Autodesk Fusion 360 part; units mm, degrees
(part 9 of 28)
  line L943 (81.3236, 21.4891) -> (81.4328, 21.505)
  line L944 (81.4328, 21.505) -> (82.9265, 21.505)
  line L945 (82.9265, 21.505) -> (88.0242, 26.6027)
  line L946 (88.0242, 26.6027) -> (88.0832, 26.6545)
  line L947 (88.0832, 26.6545) -> (88.2189, 26.7328)
  line L948 (88.2189, 26.7328) -> (88.3702, 26.7733)
  line L949 (88.3702, 26.7733) -> (88.4485, 26.7785)
  line L950 (88.4485, 26.7785) -> (102.7125, 26.7785)
  line L951 (102.7125, 26.7785) -> (102.7355, 26.8129)
  line L952 (102.7355, 26.8129) -> (102.8741, 26.9515)
  line L953 (102.8741, 26.9515) -> (103.0371, 27.0604)
  line L954 (103.0371, 27.0604) -> (103.2182, 27.1354)
  line L955 (103.2182, 27.1354) -> (103.4105, 27.1737)
  line L956 (103.4105, 27.1737) -> (103.5085, 27.1785)
  line L957 (103.5085, 27.1785) -> (104.7085, 27.1785)
  line L958 (104.7085, 27.1785) -> (104.8065, 27.1737)
  line L959 (104.8065, 27.1737) -> (104.9988, 27.1354)
  line L960 (104.9988, 27.1354) -> (105.1799, 27.0604)
  line L961 (105.1799, 27.0604) -> (105.3429, 26.9515)
  line L962 (105.3429, 26.9515) -> (105.4815, 26.8129)
  line L963 (105.4815, 26.8129) -> (105.5045, 26.7785)
  line L964 (105.5045, 26.7785) -> (107.3522, 26.7785)
  line L965 (107.3522, 26.7785) -> (107.9218, 27.3481)
  line L966 (107.9218, 27.3481) -> (107.9808, 27.3998)
  line L967 (107.9808, 27.3998) -> (108.1165, 27.4782)
  line L968 (108.1165, 27.4782) -> (108.2678, 27.5187)
  line L969 (108.2678, 27.5187) -> (108.3461, 27.5238)
  line L970 (108.3461, 27.5238) -> (112.2749, 27.5238)
  line L971 (112.2749, 27.5238) -> (112.3532, 27.5187)
  line L972 (32.7136, 22.7426) -> (32.9001, 22.682)
  line L973 (32.9001, 22.682) -> (33.0749, 22.5929)
  line L974 (33.0749, 22.5929) -> (33.2336, 22.4776)
  line L975 (33.2336, 22.4776) -> (33.3723, 22.3389)
  line L976 (33.3723, 22.3389) -> (33.4876, 22.1802)
  line L977 (33.4876, 22.1802) -> (33.5766, 22.0055)
  line L978 (33.5766, 22.0055) -> (33.6372, 21.8189)
  line L979 (33.6372, 21.8189) -> (33.6679, 21.6252)
  line L980 (33.6679, 21.6252) -> (33.6718, 21.5271)
  line L981 (33.6718, 21.5271) -> (33.6718, 21.0271)
  line L982 (33.6718, 21.0271) -> (33.6679, 20.929)
  line L983 (33.6679, 20.929) -> (33.6372, 20.7353)
  line L984 (33.6372, 20.7353) -> (33.5766, 20.5488)
  line L985 (33.5766, 20.5488) -> (33.4876, 20.374)
  line L986 (33.4876, 20.374) -> (33.3723, 20.2153)
  line L987 (33.3723, 20.2153) -> (33.2336, 20.0766)
  line L988 (33.2336, 20.0766) -> (33.0749, 19.9613)
  line L989 (33.0749, 19.9613) -> (32.9001, 19.8723)
  line L990 (32.9001, 19.8723) -> (32.7136, 19.8117)
  line L991 (32.7136, 19.8117) -> (32.5198, 19.781)
  line L992 (32.5198, 19.781) -> (32.3237, 19.781)
  line L993 (32.3237, 19.781) -> (32.13, 19.8117)
  line L994 (32.13, 19.8117) -> (31.9434, 19.8723)
  line L995 (31.9434, 19.8723) -> (31.7686, 19.9613)
  line L996 (31.7686, 19.9613) -> (31.61, 20.0766)
  line L997 (31.61, 20.0766) -> (31.4713, 20.2153)
  line L998 (31.4713, 20.2153) -> (31.356, 20.374)
  line L999 (31.356, 20.374) -> (31.2669, 20.5488)
  line L1000 (31.2669, 20.5488) -> (31.2063, 20.7353)
  line L1001 (31.2063, 20.7353) -> (31.1756, 20.929)
  line L1002 (31.1756, 20.929) -> (31.1718, 21.0271)
  line L1003 (31.1718, 21.0271) -> (31.1718, 21.5271)
  line L1004 (31.1718, 21.5271) -> (31.1756, 21.6252)
  line L1005 (31.1756, 21.6252) -> (31.2063, 21.8189)
  line L1006 (31.2063, 21.8189) -> (31.2669, 22.0055)
  line L1007 (31.2669, 22.0055) -> (31.356, 22.1802)
  line L1008 (31.356, 22.1802) -> (31.4713, 22.3389)
  line L1009 (31.4713, 22.3389) -> (31.61, 22.4776)
  line L1010 (31.61, 22.4776) -> (31.7686, 22.5929)
  line L1011 (31.7686, 22.5929) -> (31.9434, 22.682)
  line L1012 (31.9434, 22.682) -> (32.13, 22.7426)
  line L1013 (32.13, 22.7426) -> (32.3237, 22.7733)
  line L1014 (32.3237, 22.7733) -> (32.5198, 22.7733)
  line L1015 (32.5198, 22.7733) -> (32.7136, 22.7426)
  line L1016 (93.6736, 22.7426) -> (93.8601, 22.682)
  line L1017 (93.8601, 22.682) -> (94.0349, 22.5929)
  line L1018 (94.0349, 22.5929) -> (94.1936, 22.4776)
  line L1019 (94.1936, 22.4776) -> (94.3323, 22.3389)
  line L1020 (94.3323, 22.3389) -> (94.4476, 22.1802)
  line L1021 (94.4476, 22.1802) -> (94.5366, 22.0055)
  line L1022 (94.5366, 22.0055) -> (94.5972, 21.8189)
  line L1023 (94.5972, 21.8189) -> (94.6279, 21.6252)
  line L1024 (94.6279, 21.6252) -> (94.6318, 21.5271)
  line L1025 (94.6318, 21.5271) -> (94.6318, 21.0271)
  line L1026 (94.6318, 21.0271) -> (94.6279, 20.929)
  line L1027 (94.6279, 20.929) -> (94.5972, 20.7353)
  line L1028 (94.5972, 20.7353) -> (94.5366, 20.5488)
  line L1029 (94.5366, 20.5488) -> (94.4476, 20.374)
  line L1030 (94.4476, 20.374) -> (94.3323, 20.2153)
  line L1031 (94.3323, 20.2153) -> (94.1936, 20.0766)
  line L1032 (94.1936, 20.0766) -> (94.0349, 19.9613)
  line L1033 (94.0349, 19.9613) -> (93.8601, 19.8723)
  line L1034 (93.8601, 19.8723) -> (93.6736, 19.8117)
  line L1035 (93.6736, 19.8117) -> (93.4798, 19.781)
  line L1036 (93.4798, 19.781) -> (93.2837, 19.781)
  line L1037 (93.2837, 19.781) -> (93.09, 19.8117)
  line L1038 (93.09, 19.8117) -> (92.9034, 19.8723)
  line L1039 (92.9034, 19.8723) -> (92.7286, 19.9613)
  line L1040 (92.7286, 19.9613) -> (92.57, 20.0766)
  line L1041 (92.57, 20.0766) -> (92.4313, 20.2153)
  line L1042 (92.4313, 20.2153) -> (92.316, 20.374)
  line L1043 (92.316, 20.374) -> (92.2269, 20.5488)
  line L1044 (92.2269, 20.5488) -> (92.1663, 20.7353)
  line L1045 (92.1663, 20.7353) -> (92.1356, 20.929)
  line L1046 (92.1356, 20.929) -> (92.1318, 21.0271)
  line L1047 (92.1318, 21.0271) -> (92.1318, 21.5271)
  line L1048 (92.1318, 21.5271) -> (92.1356, 21.6252)
  line L1049 (92.1356, 21.6252) -> (92.1663, 21.8189)
  line L1050 (92.1663, 21.8189) -> (92.2269, 22.0055)
  line L1051 (92.2269, 22.0055) -> (92.316, 22.1802)
  line L1052 (92.316, 22.1802) -> (92.4313, 22.3389)
  line L1053 (92.4313, 22.3389) -> (92.57, 22.4776)
  line L1054 (92.57, 22.4776) -> (92.7286, 22.5929)
  line L1055 (92.7286, 22.5929) -> (92.9034, 22.682)
  line L1056 (92.9034, 22.682) -> (93.09, 22.7426)
  line L1057 (93.09, 22.7426) -> (93.2837, 22.7733)
  line L1058 (93.2837, 22.7733) -> (93.4798, 22.7733)
  line L1059 (93.4798, 22.7733) -> (93.6736, 22.7426)
  line L1060 (44.6903, 20.1434) -> (41.4903, 20.1434)
  line L1061 (41.4903, 20.1434) -> (41.4903, 22.1434)
  line L1062 (41.4903, 22.1434) -> (44.6903, 22.1434)
  line L1063 (44.6903, 22.1434) -> (44.6903, 20.1434)
  line L1064 (105.6503, 20.1434) -> (102.4503, 20.1434)
  line L1065 (102.4503, 20.1434) -> (102.4503, 22.1434)
  line L1066 (102.4503, 22.1434) -> (105.6503, 22.1434)
  line L1067 (105.6503, 22.1434) -> (105.6503, 20.1434)
  line L1068 (50.1338, 32.4063) -> (50.3204, 32.3457)
  line L1069 (50.3204, 32.3457) -> (50.4952, 32.2566)
  line L1070 (50.4952, 32.2566) -> (50.6538, 32.1413)
  line L1071 (50.6538, 32.1413) -> (50.7925, 32.0026)
  line L1072 (50.7925, 32.0026) -> (50.9078, 31.8439)
  line L1073 (50.9078, 31.8439) -> (50.9969, 31.6692)
  line L1074 (50.9969, 31.6692) -> (51.0386, 31.5408)
  line L1075 (51.0386, 31.5408) -> (52.8792, 31.5408)
  line L1076 (52.8792, 31.5408) -> (52.9575, 31.5357)
  line L1077 (52.9575, 31.5357) -> (53.1088, 31.4951)
  line L1078 (53.1088, 31.4951) -> (53.2444, 31.4168)
  line L1079 (53.2444, 31.4168) -> (53.3035, 31.3651)
  line L1080 (53.3035, 31.3651) -> (59.2476, 25.421)
  line L1081 (59.2476, 25.421) -> (59.2993, 25.3619)
  line L1082 (59.2993, 25.3619) -> (59.3373, 25.2962)
  line L1083 (59.3373, 25.2962) -> (59.3843, 25.2888)
  line L1084 (59.3843, 25.2888) -> (59.5671, 25.2294)
  line L1085 (59.5671, 25.2294) -> (59.7384, 25.1421)
  line L1086 (59.7384, 25.1421) -> (59.8939, 25.0291)
  line L1087 (59.8939, 25.0291) -> (60.0298, 24.8932)
  line L1088 (60.0298, 24.8932) -> (60.1428, 24.7377)
  line L1089 (60.1428, 24.7377) -> (60.2301, 24.5664)
  line L1090 (60.2301, 24.5664) -> (60.2895, 24.3836)
  line L1091 (60.2895, 24.3836) -> (60.3195, 24.1937)
  line L1092 (60.3195, 24.1937) -> (60.3195, 24.0015)
  line L1093 (60.3195, 24.0015) -> (60.2895, 23.8117)
  line L1094 (60.2895, 23.8117) -> (60.2301, 23.6288)
  line L1095 (60.2301, 23.6288) -> (60.1428, 23.4576)
  line L1096 (60.1428, 23.4576) -> (60.0298, 23.3021)
  line L1097 (60.0298, 23.3021) -> (59.8939, 23.1661)
  line L1098 (59.8939, 23.1661) -> (59.7384, 23.0531)
  line L1099 (59.7384, 23.0531) -> (59.5671, 22.9659)
  line L1100 (59.5671, 22.9659) -> (59.3843, 22.9065)
  line L1101 (59.3843, 22.9065) -> (59.1944, 22.8764)
  line L1102 (59.1944, 22.8764) -> (59.0983, 22.8726)
  line L1103 (59.0983, 22.8726) -> (58.5483, 22.8726)
  line L1104 (58.5483, 22.8726) -> (58.4522, 22.8764)
  line L1105 (58.4522, 22.8764) -> (58.2623, 22.9065)
  line L1106 (58.2623, 22.9065) -> (58.0795, 22.9659)
  line L1107 (58.0795, 22.9659) -> (57.9083, 23.0531)
  line L1108 (57.9083, 23.0531) -> (57.7527, 23.1661)
  line L1109 (57.7527, 23.1661) -> (57.6168, 23.3021)
  line L1110 (57.6168, 23.3021) -> (57.5038, 23.4576)
  line L1111 (57.5038, 23.4576) -> (57.4166, 23.6288)
  line L1112 (57.4166, 23.6288) -> (57.3572, 23.8117)
  line L1113 (57.3572, 23.8117) -> (57.3271, 24.0015)
  line L1114 (57.3271, 24.0015) -> (57.3271, 24.1937)
  line L1115 (57.3271, 24.1937) -> (57.3572, 24.3836)
  line L1116 (57.3572, 24.3836) -> (57.4166, 24.5664)
  line L1117 (57.4166, 24.5664) -> (57.5038, 24.7377)
  line L1118 (57.5038, 24.7377) -> (57.6168, 24.8932)
  line L1119 (57.6168, 24.8932) -> (57.7527, 25.0291)
  line L1120 (57.7527, 25.0291) -> (57.8626, 25.1089)
  line L1121 (57.8626, 25.1089) -> (52.6307, 30.3408)
  line L1122 (52.6307, 30.3408) -> (51.0386, 30.3408)
  line L1123 (51.0386, 30.3408) -> (50.9969, 30.2125)
  line L1124 (50.9969, 30.2125) -> (50.9078, 30.0377)
  line L1125 (50.9078, 30.0377) -> (50.7925, 29.879)
  line L1126 (50.7925, 29.879) -> (50.6538, 29.7403)
  line L1127 (50.6538, 29.7403) -> (50.4952, 29.625)
  line L1128 (50.4952, 29.625) -> (50.3204, 29.536)
  line L1129 (50.3204, 29.536) -> (50.1338, 29.4754)
  line L1130 (50.1338, 29.4754) -> (49.9401, 29.4447)
  line L1131 (49.9401, 29.4447) -> (49.744, 29.4447)
  line L1132 (49.744, 29.4447) -> (49.5502, 29.4754)
  line L1133 (49.5502, 29.4754) -> (49.3637, 29.536)
  line L1134 (49.3637, 29.536) -> (49.1889, 29.625)
  line L1135 (49.1889, 29.625) -> (49.0302, 29.7403)
  line L1136 (49.0302, 29.7403) -> (48.8915, 29.879)
  line L1137 (48.8915, 29.879) -> (48.7762, 30.0377)
  line L1138 (48.7762, 30.0377) -> (48.6872, 30.2125)
  line L1139 (48.6872, 30.2125) -> (48.6266, 30.399)
  line L1140 (48.6266, 30.399) -> (48.5959, 30.5927)
  line L1141 (48.5959, 30.5927) -> (48.592, 30.6908)
  line L1142 (48.592, 30.6908) -> (48.592, 31.1908)
  line L1143 (48.592, 31.1908) -> (48.5959, 31.2889)
  line L1144 (48.5959, 31.2889) -> (48.6266, 31.4826)
  line L1145 (48.6266, 31.4826) -> (48.6872, 31.6692)
  line L1146 (48.6872, 31.6692) -> (48.7762, 31.8439)
  line L1147 (48.7762, 31.8439) -> (48.8915, 32.0026)
  line L1148 (48.8915, 32.0026) -> (49.0302, 32.1413)
  line L1149 (49.0302, 32.1413) -> (49.1889, 32.2566)
  line L1150 (49.1889, 32.2566) -> (49.3637, 32.3457)
  line L1151 (49.3637, 32.3457) -> (49.5502, 32.4063)
  line L1152 (49.5502, 32.4063) -> (49.744, 32.437)
  line L1153 (49.744, 32.437) -> (49.9401, 32.437)
  line L1154 (49.9401, 32.437) -> (50.1338, 32.4063)
  line L1155 (111.0938, 32.4063) -> (111.2804, 32.3457)
  line L1156 (111.2804, 32.3457) -> (111.4552, 32.2566)
  line L1157 (111.4552, 32.2566) -> (111.6138, 32.1413)
  line L1158 (111.6138, 32.1413) -> (111.7525, 32.0026)
  line L1159 (111.7525, 32.0026) -> (111.8678, 31.8439)
  line L1160 (111.8678, 31.8439) -> (111.9569, 31.6692)
  line L1161 (111.9569, 31.6692) -> (111.9986, 31.5408)
  line L1162 (111.9986, 31.5408) -> (113.8392, 31.5408)
  line L1163 (113.8392, 31.5408) -> (113.9175, 31.5357)
  line L1164 (113.9175, 31.5357) -> (114.0688, 31.4951)
  line L1165 (114.0688, 31.4951) -> (114.2044, 31.4168)
  line L1166 (114.2044, 31.4168) -> (114.2635, 31.3651)
  line L1167 (114.2635, 31.3651) -> (120.2076, 25.421)
  line L1168 (120.2076, 25.421) -> (120.2593, 25.3619)
  line L1169 (120.2593, 25.3619) -> (120.2973, 25.2962)
  line L1170 (120.2973, 25.2962) -> (120.3443, 25.2888)
  line L1171 (120.3443, 25.2888) -> (120.5271, 25.2294)
  line L1172 (120.5271, 25.2294) -> (120.6984, 25.1421)
  line L1173 (120.6984, 25.1421) -> (120.8539, 25.0291)
  line L1174 (120.8539, 25.0291) -> (120.9898, 24.8932)
  line L1175 (120.9898, 24.8932) -> (121.1028, 24.7377)
  line L1176 (121.1028, 24.7377) -> (121.1901, 24.5664)
  line L1177 (121.1901, 24.5664) -> (121.2495, 24.3836)
  line L1178 (121.2495, 24.3836) -> (121.2795, 24.1937)
  line L1179 (121.2795, 24.1937) -> (121.2795, 24.0015)
  line L1180 (121.2795, 24.0015) -> (121.2495, 23.8117)
  line L1181 (121.2495, 23.8117) -> (121.1901, 23.6288)
  line L1182 (121.1901, 23.6288) -> (121.1028, 23.4576)
  line L1183 (121.1028, 23.4576) -> (120.9898, 23.3021)
  line L1184 (120.9898, 23.3021) -> (120.8539, 23.1661)
  line L1185 (120.8539, 23.1661) -> (120.6984, 23.0531)
  line L1186 (120.6984, 23.0531) -> (120.5271, 22.9659)
  line L1187 (120.5271, 22.9659) -> (120.3443, 22.9065)
  line L1188 (120.3443, 22.9065) -> (120.1544, 22.8764)
  line L1189 (120.1544, 22.8764) -> (120.0583, 22.8726)
  line L1190 (120.0583, 22.8726) -> (119.5083, 22.8726)
  line L1191 (119.5083, 22.8726) -> (119.4122, 22.8764)
  line L1192 (119.4122, 22.8764) -> (119.2223, 22.9065)
  line L1193 (119.2223, 22.9065) -> (119.0395, 22.9659)
  line L1194 (119.0395, 22.9659) -> (118.8683, 23.0531)
  line L1195 (118.8683, 23.0531) -> (118.7127, 23.1661)
  line L1196 (118.7127, 23.1661) -> (118.5768, 23.3021)
  line L1197 (118.5768, 23.3021) -> (118.4638, 23.4576)
  line L1198 (118.4638, 23.4576) -> (118.3766, 23.6288)
  line L1199 (118.3766, 23.6288) -> (118.3172, 23.8117)
  line L1200 (118.3172, 23.8117) -> (118.2871, 24.0015)
  line L1201 (118.2871, 24.0015) -> (118.2871, 24.1937)
  line L1202 (118.2871, 24.1937) -> (118.3172, 24.3836)
  line L1203 (118.3172, 24.3836) -> (118.3766, 24.5664)
  line L1204 (118.3766, 24.5664) -> (118.4638, 24.7377)
  line L1205 (118.4638, 24.7377) -> (118.5768, 24.8932)
  line L1206 (118.5768, 24.8932) -> (118.7127, 25.0291)
  line L1207 (118.7127, 25.0291) -> (118.8226, 25.1089)
  line L1208 (118.8226, 25.1089) -> (113.5907, 30.3408)
  line L1209 (113.5907, 30.3408) -> (111.9986, 30.3408)
  line L1210 (111.9986, 30.3408) -> (111.9569, 30.2125)
  line L1211 (111.9569, 30.2125) -> (111.8678, 30.0377)
  line L1212 (111.8678, 30.0377) -> (111.7525, 29.879)
  line L1213 (111.7525, 29.879) -> (111.6138, 29.7403)
  line L1214 (111.6138, 29.7403) -> (111.4552, 29.625)
  line L1215 (111.4552, 29.625) -> (111.2804, 29.536)
  line L1216 (111.2804, 29.536) -> (111.0938, 29.4754)
  line L1217 (111.0938, 29.4754) -> (110.9001, 29.4447)
  line L1218 (110.9001, 29.4447) -> (110.704, 29.4447)
  line L1219 (110.704, 29.4447) -> (110.5102, 29.4754)
  line L1220 (110.5102, 29.4754) -> (110.3237, 29.536)
  line L1221 (110.3237, 29.536) -> (110.1489, 29.625)
  line L1222 (110.1489, 29.625) -> (109.9902, 29.7403)
  line L1223 (109.9902, 29.7403) -> (109.8515, 29.879)
  line L1224 (109.8515, 29.879) -> (109.7362, 30.0377)
  line L1225 (109.7362, 30.0377) -> (109.6472, 30.2125)
  line L1226 (109.6472, 30.2125) -> (109.5866, 30.399)
  line L1227 (109.5866, 30.399) -> (109.5559, 30.5927)
  line L1228 (109.5559, 30.5927) -> (109.552, 30.6908)
  line L1229 (109.552, 30.6908) -> (109.552, 31.1908)
  line L1230 (109.552, 31.1908) -> (109.5559, 31.2889)
  line L1231 (109.5559, 31.2889) -> (109.5866, 31.4826)
  line L1232 (109.5866, 31.4826) -> (109.6472, 31.6692)
  line L1233 (109.6472, 31.6692) -> (109.7362, 31.8439)
  line L1234 (109.7362, 31.8439) -> (109.8515, 32.0026)
  line L1235 (109.8515, 32.0026) -> (109.9902, 32.1413)
  line L1236 (109.9902, 32.1413) -> (110.1489, 32.2566)
  line L1237 (110.1489, 32.2566) -> (110.3237, 32.3457)
  line L1238 (110.3237, 32.3457) -> (110.5102, 32.4063)
  line L1239 (110.5102, 32.4063) -> (110.704, 32.437)
  line L1240 (110.704, 32.437) -> (110.9001, 32.437)
  line L1241 (110.9001, 32.437) -> (111.0938, 32.4063)
  line L1242 (32.7136, 30.3626) -> (32.9001, 30.302)
  line L1243 (32.9001, 30.302) -> (33.0749, 30.2129)
  line L1244 (33.0749, 30.2129) -> (33.2336, 30.0976)
  line L1245 (33.2336, 30.0976) -> (33.3723, 29.9589)
  line L1246 (33.3723, 29.9589) -> (33.4876, 29.8002)
  line L1247 (33.4876, 29.8002) -> (33.5766, 29.6255)
  line L1248 (33.5766, 29.6255) -> (33.6372, 29.4389)
  line L1249 (33.6372, 29.4389) -> (33.6679, 29.2452)
  line L1250 (33.6679, 29.2452) -> (33.6718, 29.1471)
  line L1251 (33.6718, 29.1471) -> (33.6718, 28.6471)
  line L1252 (33.6718, 28.6471) -> (33.6679, 28.549)
  line L1253 (33.6679, 28.549) -> (33.6372, 28.3553)
  line L1254 (33.6372, 28.3553) -> (33.5766, 28.1688)
  line L1255 (33.5766, 28.1688) -> (33.4876, 27.994)
  line L1256 (33.4876, 27.994) -> (33.3723, 27.8353)
  line L1257 (33.3723, 27.8353) -> (33.2336, 27.6966)
  line L1258 (33.2336, 27.6966) -> (33.0749, 27.5813)
  line L1259 (33.0749, 27.5813) -> (32.9001, 27.4923)
  line L1260 (32.9001, 27.4923) -> (32.7136, 27.4317)
  line L1261 (32.7136, 27.4317) -> (32.5198, 27.401)
  line L1262 (32.5198, 27.401) -> (32.3237, 27.401)
  line L1263 (32.3237, 27.401) -> (32.13, 27.4317)
  line L1264 (32.13, 27.4317) -> (31.9434, 27.4923)
  line L1265 (31.9434, 27.4923) -> (31.7686, 27.5813)
  line L1266 (31.7686, 27.5813) -> (31.61, 27.6966)
  line L1267 (31.61, 27.6966) -> (31.4713, 27.8353)
  line L1268 (31.4713, 27.8353) -> (31.356, 27.994)
  line L1269 (31.356, 27.994) -> (31.2669, 28.1688)
  line L1270 (31.2669, 28.1688) -> (31.2063, 28.3553)
  line L1271 (31.2063, 28.3553) -> (31.1756, 28.549)
  line L1272 (31.1756, 28.549) -> (31.1718, 28.6471)
  line L1273 (31.1718, 28.6471) -> (31.1718, 29.1471)
  line L1274 (31.1718, 29.1471) -> (31.1756, 29.2452)
  line L1275 (31.1756, 29.2452) -> (31.2063, 29.4389)
  line L1276 (31.2063, 29.4389) -> (31.2669, 29.6255)
  line L1277 (31.2669, 29.6255) -> (31.356, 29.8002)
  line L1278 (31.356, 29.8002) -> (31.4713, 29.9589)
  line L1279 (31.4713, 29.9589) -> (31.61, 30.0976)
  line L1280 (31.61, 30.0976) -> (31.7686, 30.2129)
  line L1281 (31.7686, 30.2129) -> (31.9434, 30.302)
  line L1282 (31.9434, 30.302) -> (32.13, 30.3626)
  line L1283 (32.13, 30.3626) -> (32.3237, 30.3933)
  line L1284 (32.3237, 30.3933) -> (32.5198, 30.3933)
  line L1285 (32.5198, 30.3933) -> (32.7136, 30.3626)
  line L1286 (93.6736, 30.3626) -> (93.8601, 30.302)
  line L1287 (93.8601, 30.302) -> (94.0349, 30.2129)
  line L1288 (94.0349, 30.2129) -> (94.1936, 30.0976)
  line L1289 (94.1936, 30.0976) -> (94.3323, 29.9589)
  line L1290 (94.3323, 29.9589) -> (94.4476, 29.8002)
  line L1291 (94.4476, 29.8002) -> (94.5366, 29.6255)
  line L1292 (94.5366, 29.6255) -> (94.5972, 29.4389)
  line L1293 (94.5972, 29.4389) -> (94.6279, 29.2452)
  line L1294 (94.6279, 29.2452) -> (94.6318, 29.1471)
  line L1295 (94.6318, 29.1471) -> (94.6318, 28.6471)
  line L1296 (94.6318, 28.6471) -> (94.6279, 28.549)
  line L1297 (94.6279, 28.549) -> (94.5972, 28.3553)
  line L1298 (94.5972, 28.3553) -> (94.5366, 28.1688)
  line L1299 (94.5366, 28.1688) -> (94.4476, 27.994)
  line L1300 (94.4476, 27.994) -> (94.3323, 27.8353)
  line L1301 (94.3323, 27.8353) -> (94.1936, 27.6966)
  line L1302 (94.1936, 27.6966) -> (94.0349, 27.5813)
  line L1303 (94.0349, 27.5813) -> (93.8601, 27.4923)
  line L1304 (93.8601, 27.4923) -> (93.6736, 27.4317)
  line L1305 (93.6736, 27.4317) -> (93.4798, 27.401)
  line L1306 (93.4798, 27.401) -> (93.2837, 27.401)
  line L1307 (93.2837, 27.401) -> (93.09, 27.4317)
  line L1308 (93.09, 27.4317) -> (92.9034, 27.4923)
  line L1309 (92.9034, 27.4923) -> (92.7286, 27.5813)
  line L1310 (92.7286, 27.5813) -> (92.57, 27.6966)
  line L1311 (92.57, 27.6966) -> (92.4313, 27.8353)
  line L1312 (92.4313, 27.8353) -> (92.316, 27.994)
  line L1313 (92.316, 27.994) -> (92.2269, 28.1688)
  line L1314 (92.2269, 28.1688) -> (92.1663, 28.3553)
  line L1315 (92.1663, 28.3553) -> (92.1356, 28.549)
  line L1316 (92.1356, 28.549) -> (92.1318, 28.6471)
  line L1317 (92.1318, 28.6471) -> (92.1318, 29.1471)
  line L1318 (92.1318, 29.1471) -> (92.1356, 29.2452)
  line L1319 (92.1356, 29.2452) -> (92.1663, 29.4389)
  line L1320 (92.1663, 29.4389) -> (92.2269, 29.6255)
  line L1321 (92.2269, 29.6255) -> (92.316, 29.8002)
  line L1322 (92.316, 29.8002) -> (92.4313, 29.9589)
  line L1323 (92.4313, 29.9589) -> (92.57, 30.0976)
  line L1324 (92.57, 30.0976) -> (92.7286, 30.2129)
  line L1325 (92.7286, 30.2129) -> (92.9034, 30.302)
  line L1326 (92.9034, 30.302) -> (93.09, 30.3626)
  line L1327 (93.09, 30.3626) -> (93.2837, 30.3933)
  line L1328 (93.2837, 30.3933) -> (93.4798, 30.3933)
  line L1329 (93.4798, 30.3933) -> (93.6736, 30.3626)
  line L1330 (22.3742, 30.1765) -> (22.5641, 30.1465)
  line L1331 (22.5641, 30.1465) -> (22.7469, 30.0871)
  line L1332 (22.7469, 30.0871) -> (22.9182, 29.9998)
  line L1333 (22.9182, 29.9998) -> (23.0737, 29.8868)
  line L1334 (23.0737, 29.8868) -> (23.2096, 29.7509)
  line L1335 (23.2096, 29.7509) -> (23.3226, 29.5954)
  line L1336 (23.3226, 29.5954) -> (23.4099, 29.4241)
  line L1337 (23.4099, 29.4241) -> (23.4693, 29.2413)
  line L1338 (23.4693, 29.2413) -> (23.4993, 29.0514)
  line L1339 (23.4993, 29.0514) -> (23.4993, 28.8592)
  line L1340 (23.4993, 28.8592) -> (23.4693, 28.6693)
  line L1341 (23.4693, 28.6693) -> (23.4099, 28.4865)
  line L1342 (23.4099, 28.4865) -> (23.3226, 28.3153)
  line L1343 (23.3226, 28.3153) -> (23.2096, 28.1597)
  line L1344 (23.2096, 28.1597) -> (23.0737, 28.0238)
  line L1345 (23.0737, 28.0238) -> (22.9182, 27.9108)
  line L1346 (22.9182, 27.9108) -> (22.7469, 27.8236)
  line L1347 (22.7469, 27.8236) -> (22.5641, 27.7642)
  line L1348 (22.5641, 27.7642) -> (22.3742, 27.7341)
  line L1349 (22.3742, 27.7341) -> (22.2781, 27.7303)
  line L1350 (22.2781, 27.7303) -> (21.7281, 27.7303)
  line L1351 (21.7281, 27.7303) -> (21.632, 27.7341)
  line L1352 (21.632, 27.7341) -> (21.4421, 27.7642)
  line L1353 (21.4421, 27.7642) -> (21.2593, 27.8236)
  line L1354 (21.2593, 27.8236) -> (21.0881, 27.9108)
  line L1355 (21.0881, 27.9108) -> (20.9325, 28.0238)
  line L1356 (20.9325, 28.0238) -> (20.7966, 28.1597)
  line L1357 (20.7966, 28.1597) -> (20.6836, 28.3153)
  line L1358 (20.6836, 28.3153) -> (20.5964, 28.4865)
  line L1359 (20.5964, 28.4865) -> (20.537, 28.6693)
  line L1360 (20.537, 28.6693) -> (20.5069, 28.8592)
  line L1361 (20.5069, 28.8592) -> (20.5069, 29.0514)
  line L1362 (20.5069, 29.0514) -> (20.537, 29.2413)
  line L1363 (20.537, 29.2413) -> (20.5964, 29.4241)
  line L1364 (20.5964, 29.4241) -> (20.6836, 29.5954)
  line L1365 (20.6836, 29.5954) -> (20.7966, 29.7509)
  line L1366 (20.7966, 29.7509) -> (20.9325, 29.8868)
  line L1367 (20.9325, 29.8868) -> (21.0881, 29.9998)
  line L1368 (21.0881, 29.9998) -> (21.2593, 30.0871)
  line L1369 (21.2593, 30.0871) -> (21.4421, 30.1465)
  line L1370 (21.4421, 30.1465) -> (21.632, 30.1765)
  line L1371 (21.632, 30.1765) -> (21.7281, 30.1803)
  line L1372 (21.7281, 30.1803) -> (22.2781, 30.1803)
  line L1373 (22.2781, 30.1803) -> (22.3742, 30.1765)
  line L1374 (83.3342, 30.1765) -> (83.5241, 30.1465)
  line L1375 (83.5241, 30.1465) -> (83.7069, 30.0871)
  line L1376 (83.7069, 30.0871) -> (83.8782, 29.9998)
  line L1377 (83.8782, 29.9998) -> (84.0337, 29.8868)
  line L1378 (84.0337, 29.8868) -> (84.1696, 29.7509)
  line L1379 (84.1696, 29.7509) -> (84.2826, 29.5954)
  line L1380 (84.2826, 29.5954) -> (84.3699, 29.4241)
  line L1381 (84.3699, 29.4241) -> (84.4293, 29.2413)
  line L1382 (84.4293, 29.2413) -> (84.4593, 29.0514)
  line L1383 (84.4593, 29.0514) -> (84.4593, 28.8592)
  line L1384 (84.4593, 28.8592) -> (84.4293, 28.6693)
  line L1385 (84.4293, 28.6693) -> (84.3699, 28.4865)
  line L1386 (84.3699, 28.4865) -> (84.2826, 28.3153)
  line L1387 (84.2826, 28.3153) -> (84.1696, 28.1597)
  line L1388 (84.1696, 28.1597) -> (84.0337, 28.0238)
  line L1389 (84.0337, 28.0238) -> (83.8782, 27.9108)
  line L1390 (83.8782, 27.9108) -> (83.7069, 27.8236)
  line L1391 (83.7069, 27.8236) -> (83.5241, 27.7642)
  line L1392 (83.5241, 27.7642) -> (83.3342, 27.7341)
  line L1393 (83.3342, 27.7341) -> (83.2381, 27.7303)
  line L1394 (83.2381, 27.7303) -> (82.6881, 27.7303)
  line L1395 (82.6881, 27.7303) -> (82.592, 27.7341)
  line L1396 (82.592, 27.7341) -> (82.4021, 27.7642)
  line L1397 (82.4021, 27.7642) -> (82.2193, 27.8236)
  line L1398 (82.2193, 27.8236) -> (82.0481, 27.9108)
  line L1399 (82.0481, 27.9108) -> (81.8925, 28.0238)
  line L1400 (81.8925, 28.0238) -> (81.7566, 28.1597)
  line L1401 (81.7566, 28.1597) -> (81.6436, 28.3153)
  line L1402 (81.6436, 28.3153) -> (81.5564, 28.4865)
  line L1403 (81.5564, 28.4865) -> (81.497, 28.6693)
  line L1404 (81.497, 28.6693) -> (81.4669, 28.8592)
  line L1405 (81.4669, 28.8592) -> (81.4669, 29.0514)
  line L1406 (81.4669, 29.0514) -> (81.497, 29.2413)
  line L1407 (81.497, 29.2413) -> (81.5564, 29.4241)
  line L1408 (81.5564, 29.4241) -> (81.6436, 29.5954)
  line L1409 (81.6436, 29.5954) -> (81.7566, 29.7509)
  line L1410 (81.7566, 29.7509) -> (81.8925, 29.8868)
  line L1411 (81.8925, 29.8868) -> (82.0481, 29.9998)
  line L1412 (82.0481, 29.9998) -> (82.2193, 30.0871)
  line L1413 (82.2193, 30.0871) -> (82.4021, 30.1465)
  line L1414 (82.4021, 30.1465) -> (82.592, 30.1765)
  line L1415 (82.592, 30.1765) -> (82.6881, 30.1803)
  line L1416 (82.6881, 30.1803) -> (83.2381, 30.1803)
  line L1417 (83.2381, 30.1803) -> (83.3342, 30.1765)
  line L1418 (12.0488, 27.7942) -> (9.0488, 27.7942)
  line L1419 (9.0488, 27.7942) -> (9.0488, 30.2442)
  line L1420 (9.0488, 30.2442) -> (12.0488, 30.2442)
  line L1421 (12.0488, 30.2442) -> (12.0488, 27.7942)
  line L1422 (73.0088, 27.7942) -> (70.0088, 27.7942)
  line L1423 (70.0088, 27.7942) -> (70.0088, 30.2442)
  line L1424 (70.0088, 30.2442) -> (73.0088, 30.2442)
  line L1425 (73.0088, 30.2442) -> (73.0088, 27.7942)
  line L1426 (43.8465, 29.9037) -> (44.0388, 29.8654)
  line L1427 (44.0388, 29.8654) -> (44.2199, 29.7904)
  line L1428 (44.2199, 29.7904) -> (44.3829, 29.6815)
  line L1429 (44.3829, 29.6815) -> (44.5215, 29.5429)
  line L1430 (44.5215, 29.5429) -> (44.6304, 29.3799)
  line L1431 (44.6304, 29.3799) -> (44.7054, 29.1988)
  line L1432 (44.7054, 29.1988) -> (44.7437, 29.0065)
  line L1433 (44.7437, 29.0065) -> (44.7437, 28.8105)
  line L1434 (44.7437, 28.8105) -> (44.7054, 28.6182)
  line L1435 (44.7054, 28.6182) -> (44.6304, 28.4371)
  line L1436 (44.6304, 28.4371) -> (44.5215, 28.2741)
  line L1437 (44.5215, 28.2741) -> (44.3829, 28.1355)
  line L1438 (44.3829, 28.1355) -> (44.2199, 28.0266)
  line L1439 (44.2199, 28.0266) -> (44.0388, 27.9515)
  line L1440 (44.0388, 27.9515) -> (43.8465, 27.9133)
  line L1441 (43.8465, 27.9133) -> (43.7485, 27.9085)
  line L1442 (43.7485, 27.9085) -> (42.5485, 27.9085)
  line L1443 (42.5485, 27.9085) -> (42.4505, 27.9133)
  line L1444 (42.4505, 27.9133) -> (42.2582, 27.9515)
  line L1445 (42.2582, 27.9515) -> (42.0771, 28.0266)
  line L1446 (42.0771, 28.0266) -> (41.9141, 28.1355)
  line L1447 (41.9141, 28.1355) -> (41.7755, 28.2741)
  line L1448 (41.7755, 28.2741) -> (41.6666, 28.4371)
  line L1449 (41.6666, 28.4371) -> (41.5915, 28.6182)
  line L1450 (41.5915, 28.6182) -> (41.5533, 28.8105)
  line L1451 (41.5533, 28.8105) -> (41.5533, 29.0065)
  line L1452 (41.5533, 29.0065) -> (41.5915, 29.1988)
  line L1453 (41.5915, 29.1988) -> (41.6666, 29.3799)
  line L1454 (41.6666, 29.3799) -> (41.7755, 29.5429)
  line L1455 (41.7755, 29.5429) -> (41.9141, 29.6815)
  line L1456 (41.9141, 29.6815) -> (42.0771, 29.7904)
  line L1457 (42.0771, 29.7904) -> (42.2582, 29.8654)
  line L1458 (42.2582, 29.8654) -> (42.4505, 29.9037)
  line L1459 (42.4505, 29.9037) -> (42.5485, 29.9085)
  line L1460 (42.5485, 29.9085) -> (43.7485, 29.9085)
  line L1461 (43.7485, 29.9085) -> (43.8465, 29.9037)
  line L1462 (104.8065, 29.9037) -> (104.9988, 29.8654)
  line L1463 (104.9988, 29.8654) -> (105.1799, 29.7904)
  line L1464 (105.1799, 29.7904) -> (105.3429, 29.6815)
  line L1465 (105.3429, 29.6815) -> (105.4815, 29.5429)
  line L1466 (105.4815, 29.5429) -> (105.5904, 29.3799)
  line L1467 (105.5904, 29.3799) -> (105.6654, 29.1988)
  line L1468 (105.6654, 29.1988) -> (105.7037, 29.0065)
  line L1469 (105.7037, 29.0065) -> (105.7037, 28.8105)
  line L1470 (105.7037, 28.8105) -> (105.6654, 28.6182)
  line L1471 (105.6654, 28.6182) -> (105.5904, 28.4371)
  line L1472 (105.5904, 28.4371) -> (105.4815, 28.2741)
  line L1473 (105.4815, 28.2741) -> (105.3429, 28.1355)
  line L1474 (105.3429, 28.1355) -> (105.1799, 28.0266)
  line L1475 (105.1799, 28.0266) -> (104.9988, 27.9515)
  line L1476 (104.9988, 27.9515) -> (104.8065, 27.9133)
  line L1477 (104.8065, 27.9133) -> (104.7085, 27.9085)
  line L1478 (104.7085, 27.9085) -> (103.5085, 27.9085)
  line L1479 (103.5085, 27.9085) -> (103.4105, 27.9133)
  line L1480 (103.4105, 27.9133) -> (103.2182, 27.9515)
  line L1481 (103.2182, 27.9515) -> (103.0371, 28.0266)
  line L1482 (103.0371, 28.0266) -> (102.8741, 28.1355)
  line L1483 (102.8741, 28.1355) -> (102.7355, 28.2741)
  line L1484 (102.7355, 28.2741) -> (102.6266, 28.4371)
  line L1485 (102.6266, 28.4371) -> (102.5515, 28.6182)
  line L1486 (102.5515, 28.6182) -> (102.5133, 28.8105)
  line L1487 (102.5133, 28.8105) -> (102.5133, 29.0065)
  line L1488 (102.5133, 29.0065) -> (102.5515, 29.1988)
  line L1489 (102.5515, 29.1988) -> (102.6266, 29.3799)
  line L1490 (102.6266, 29.3799) -> (102.7355, 29.5429)
  line L1491 (102.7355, 29.5429) -> (102.8741, 29.6815)
  line L1492 (102.8741, 29.6815) -> (103.0371, 29.7904)
  line L1493 (103.0371, 29.7904) -> (103.2182, 29.8654)
  line L1494 (103.2182, 29.8654) -> (103.4105, 29.9037)
  line L1495 (103.4105, 29.9037) -> (103.5085, 29.9085)
  line L1496 (103.5085, 29.9085) -> (104.7085, 29.9085)
  line L1497 (104.7085, 29.9085) -> (104.8065, 29.9037)
  line L1498 (10.9199, 32.7804) -> (11.1098, 32.7504)
  line L1499 (11.1098, 32.7504) -> (11.2926, 32.691)
  line L1500 (11.2926, 32.691) -> (11.4639, 32.6037)
  line L1501 (11.4639, 32.6037) -> (11.6194, 32.4907)
  line L1502 (11.6194, 32.4907) -> (11.7553, 32.3548)
  line L1503 (11.7553, 32.3548) -> (11.8683, 32.1993)
  line L1504 (11.8683, 32.1993) -> (11.9556, 32.028)
  line L1505 (11.9556, 32.028) -> (12.015, 31.8452)
  line L1506 (12.015, 31.8452) -> (12.0451, 31.6553)
  line L1507 (12.0451, 31.6553) -> (12.0451, 31.4631)
  line L1508 (12.0451, 31.4631) -> (12.015, 31.2732)
  line L1509 (12.015, 31.2732) -> (11.9556, 31.0904)
  line L1510 (11.9556, 31.0904) -> (11.8683, 30.9191)
  line L1511 (11.8683, 30.9191) -> (11.7553, 30.7636)
  line L1512 (11.7553, 30.7636) -> (11.6194, 30.6277)
  line L1513 (11.6194, 30.6277) -> (11.4639, 30.5147)
  line L1514 (11.4639, 30.5147) -> (11.2926, 30.4274)
  line L1515 (11.2926, 30.4274) -> (11.1098, 30.368)
  line L1516 (11.1098, 30.368) -> (10.9199, 30.338)
  line L1517 (10.9199, 30.338) -> (10.8238, 30.3342)
  line L1518 (10.8238, 30.3342) -> (10.2738, 30.3342)
  line L1519 (10.2738, 30.3342) -> (10.1777, 30.338)
  line L1520 (10.1777, 30.338) -> (9.9879, 30.368)
  line L1521 (9.9879, 30.368) -> (9.8051, 30.4274)
  line L1522 (9.8051, 30.4274) -> (9.6338, 30.5147)
  line L1523 (9.6338, 30.5147) -> (9.4783, 30.6277)
  line L1524 (9.4783, 30.6277) -> (9.3423, 30.7636)
  line L1525 (9.3423, 30.7636) -> (9.2294, 30.9191)
  line L1526 (9.2294, 30.9191) -> (9.1421, 31.0904)
  line L1527 (9.1421, 31.0904) -> (9.0827, 31.2732)
  line L1528 (9.0827, 31.2732) -> (9.0526, 31.4631)
  line L1529 (9.0526, 31.4631) -> (9.0526, 31.6553)
  line L1530 (9.0526, 31.6553) -> (9.0827, 31.8452)
  line L1531 (9.0827, 31.8452) -> (9.1421, 32.028)
  line L1532 (9.1421, 32.028) -> (9.2294, 32.1993)
  line L1533 (9.2294, 32.1993) -> (9.3423, 32.3548)
  line L1534 (9.3423, 32.3548) -> (9.4783, 32.4907)
  line L1535 (9.4783, 32.4907) -> (9.6338, 32.6037)
  line L1536 (9.6338, 32.6037) -> (9.8051, 32.691)
  line L1537 (9.8051, 32.691) -> (9.9879, 32.7504)
  line L1538 (9.9879, 32.7504) -> (10.1777, 32.7804)
  line L1539 (10.1777, 32.7804) -> (10.2738, 32.7842)
  line L1540 (10.2738, 32.7842) -> (10.8238, 32.7842)
  line L1541 (10.8238, 32.7842) -> (10.9199, 32.7804)
  line L1542 (71.8799, 32.7804) -> (72.0698, 32.7504)
  line L1543 (72.0698, 32.7504) -> (72.2526, 32.691)
  line L1544 (72.2526, 32.691) -> (72.4239, 32.6037)
  line L1545 (72.4239, 32.6037) -> (72.5794, 32.4907)
  line L1546 (72.5794, 32.4907) -> (72.7153, 32.3548)
  line L1547 (72.7153, 32.3548) -> (72.8283, 32.1993)
  line L1548 (72.8283, 32.1993) -> (72.9156, 32.028)
  line L1549 (72.9156, 32.028) -> (72.975, 31.8452)
  line L1550 (72.975, 31.8452) -> (73.0051, 31.6553)
  line L1551 (73.0051, 31.6553) -> (73.0051, 31.4631)
  line L1552 (73.0051, 31.4631) -> (72.975, 31.2732)
  line L1553 (72.975, 31.2732) -> (72.9156, 31.0904)
  line L1554 (72.9156, 31.0904) -> (72.8283, 30.9191)
  line L1555 (72.8283, 30.9191) -> (72.7153, 30.7636)
  line L1556 (72.7153, 30.7636) -> (72.5794, 30.6277)
  line L1557 (72.5794, 30.6277) -> (72.4239, 30.5147)
  line L1558 (72.4239, 30.5147) -> (72.2526, 30.4274)
  line L1559 (72.2526, 30.4274) -> (72.0698, 30.368)
  line L1560 (72.0698, 30.368) -> (71.8799, 30.338)
  line L1561 (71.8799, 30.338) -> (71.7838, 30.3342)
  line L1562 (71.7838, 30.3342) -> (71.2338, 30.3342)
  line L1563 (71.2338, 30.3342) -> (71.1377, 30.338)
  line L1564 (71.1377, 30.338) -> (70.9479, 30.368)
  line L1565 (70.9479, 30.368) -> (70.7651, 30.4274)
  line L1566 (70.7651, 30.4274) -> (70.5938, 30.5147)
  line L1567 (70.5938, 30.5147) -> (70.4383, 30.6277)
  line L1568 (70.4383, 30.6277) -> (70.3023, 30.7636)
  line L1569 (70.3023, 30.7636) -> (70.1894, 30.9191)
  line L1570 (70.1894, 30.9191) -> (70.1021, 31.0904)
  line L1571 (70.1021, 31.0904) -> (70.0427, 31.2732)
  line L1572 (70.0427, 31.2732) -> (70.0126, 31.4631)
  line L1573 (70.0126, 31.4631) -> (70.0126, 31.6553)
  line L1574 (70.0126, 31.6553) -> (70.0427, 31.8452)
  line L1575 (70.0427, 31.8452) -> (70.1021, 32.028)
  line L1576 (70.1021, 32.028) -> (70.1894, 32.1993)
  line L1577 (70.1894, 32.1993) -> (70.3023, 32.3548)
  line L1578 (70.3023, 32.3548) -> (70.4383, 32.4907)
  line L1579 (70.4383, 32.4907) -> (70.5938, 32.6037)
  line L1580 (70.5938, 32.6037) -> (70.7651, 32.691)
  line L1581 (70.7651, 32.691) -> (70.9479, 32.7504)
  line L1582 (70.9479, 32.7504) -> (71.1377, 32.7804)
  line L1583 (71.1377, 32.7804) -> (71.2338, 32.7842)
  line L1584 (71.2338, 32.7842) -> (71.7838, 32.7842)
  line L1585 (71.7838, 32.7842) -> (71.8799, 32.7804)
  line L1586 (44.7485, 30.6785) -> (41.5485, 30.6785)
  line L1587 (41.5485, 30.6785) -> (41.5485, 32.6785)
  line L1588 (41.5485, 32.6785) -> (44.7485, 32.6785)
  line L1589 (44.7485, 32.6785) -> (44.7485, 30.6785)
  line L1590 (105.7085, 30.6785) -> (102.5085, 30.6785)
  line L1591 (102.5085, 30.6785) -> (102.5085, 32.6785)
  line L1592 (102.5085, 32.6785) -> (105.7085, 32.6785)
  line L1593 (105.7085, 32.6785) -> (105.7085, 30.6785)
  line L1594 (17.2908, 40.7988) -> (14.8408, 40.7988)
  line L1595 (14.8408, 40.7988) -> (14.8408, 43.7988)
  line L1596 (14.8408, 43.7988) -> (17.2908, 43.7988)
  line L1597 (17.2908, 43.7988) -> (17.2908, 40.7988)
  line L1598 (52.2158, 40.7988) -> (49.7658, 40.7988)
  line L1599 (49.7658, 40.7988) -> (49.7658, 43.7988)
  line L1600 (49.7658, 43.7988) -> (52.2158, 43.7988)
  line L1601 (52.2158, 43.7988) -> (52.2158, 40.7988)
  line L1602 (87.1408, 40.7988) -> (84.6908, 40.7988)
  line L1603 (84.6908, 40.7988) -> (84.6908, 43.7988)
  line L1604 (84.6908, 43.7988) -> (87.1408, 43.7988)
  line L1605 (87.1408, 43.7988) -> (87.1408, 40.7988)
  line L1606 (122.0658, 40.7988) -> (119.6158, 40.7988)
  line L1607 (119.6158, 40.7988) -> (119.6158, 43.7988)
  line L1608 (119.6158, 43.7988) -> (122.0658, 43.7988)
  line L1609 (122.0658, 43.7988) -> (122.0658, 40.7988)
  line L1610 (13.8118, 43.765) -> (13.9946, 43.7056)
  line L1611 (13.9946, 43.7056) -> (14.1659, 43.6183)
  line L1612 (14.1659, 43.6183) -> (14.3214, 43.5053)
  line L1613 (14.3214, 43.5053) -> (14.4573, 43.3694)
  line L1614 (14.4573, 43.3694) -> (14.5703, 43.2139)
  line L1615 (14.5703, 43.2139) -> (14.6576, 43.0426)
  line L1616 (14.6576, 43.0426) -> (14.717, 42.8598)
  line L1617 (14.717, 42.8598) -> (14.747, 42.6699)
  line L1618 (14.747, 42.6699) -> (14.7508, 42.5738)
  line L1619 (14.7508, 42.5738) -> (14.7508, 42.0238)
  line L1620 (14.7508, 42.0238) -> (14.747, 41.9277)
  line L1621 (14.747, 41.9277) -> (14.717, 41.7379)
  line L1622 (14.717, 41.7379) -> (14.6576, 41.555)
  line L1623 (14.6576, 41.555) -> (14.5703, 41.3838)
  line L1624 (14.5703, 41.3838) -> (14.4573, 41.2283)
  line L1625 (14.4573, 41.2283) -> (14.3214, 41.0923)
  line L1626 (14.3214, 41.0923) -> (14.1659, 40.9794)
  line L1627 (14.1659, 40.9794) -> (13.9946, 40.8921)
  line L1628 (13.9946, 40.8921) -> (13.8118, 40.8327)
  line L1629 (13.8118, 40.8327) -> (13.6219, 40.8026)
  line L1630 (13.6219, 40.8026) -> (13.4297, 40.8026)
  line L1631 (13.4297, 40.8026) -> (13.2398, 40.8327)
  line L1632 (13.2398, 40.8327) -> (13.057, 40.8921)
  line L1633 (13.057, 40.8921) -> (12.8857, 40.9794)
  line L1634 (12.8857, 40.9794) -> (12.7302, 41.0923)
  line L1635 (12.7302, 41.0923) -> (12.5943, 41.2283)
  line L1636 (12.5943, 41.2283) -> (12.4813, 41.3838)
  line L1637 (12.4813, 41.3838) -> (12.394, 41.5551)
  line L1638 (12.394, 41.5551) -> (12.3346, 41.7379)
  line L1639 (12.3346, 41.7379) -> (12.3046, 41.9277)
  line L1640 (12.3046, 41.9277) -> (12.3008, 42.0238)
  line L1641 (12.3008, 42.0238) -> (12.3008, 42.5738)
  line L1642 (12.3008, 42.5738) -> (12.3046, 42.6699)
  line L1643 (12.3046, 42.6699) -> (12.3346, 42.8598)
  line L1644 (12.3346, 42.8598) -> (12.394, 43.0426)
  line L1645 (12.394, 43.0426) -> (12.4813, 43.2139)
  line L1646 (12.4813, 43.2139) -> (12.5943, 43.3694)
  line L1647 (12.5943, 43.3694) -> (12.7302, 43.5053)
  line L1648 (12.7302, 43.5053) -> (12.8857, 43.6183)
  line L1649 (12.8857, 43.6183) -> (13.057, 43.7056)
  line L1650 (13.057, 43.7056) -> (13.2398, 43.765)
  line L1651 (13.2398, 43.765) -> (13.4297, 43.7951)
  line L1652 (13.4297, 43.7951) -> (13.6219, 43.7951)
  line L1653 (13.6219, 43.7951) -> (13.8118, 43.765)
  line L1654 (48.7368, 43.765) -> (48.9196, 43.7056)
  line L1655 (48.9196, 43.7056) -> (49.0909, 43.6183)
  line L1656 (49.0909, 43.6183) -> (49.2464, 43.5053)
  line L1657 (49.2464, 43.5053) -> (49.3823, 43.3694)
  line L1658 (49.3823, 43.3694) -> (49.4953, 43.2139)
  line L1659 (49.4953, 43.2139) -> (49.5826, 43.0426)
  line L1660 (49.5826, 43.0426) -> (49.642, 42.8598)
  line L1661 (49.642, 42.8598) -> (49.672, 42.6699)
  line L1662 (49.672, 42.6699) -> (49.6758, 42.5738)
  line L1663 (49.6758, 42.5738) -> (49.6758, 42.0238)
  line L1664 (49.6758, 42.0238) -> (49.672, 41.9277)
  line L1665 (49.672, 41.9277) -> (49.642, 41.7379)
  line L1666 (49.642, 41.7379) -> (49.5826, 41.555)
  line L1667 (49.5826, 41.555) -> (49.4953, 41.3838)
  line L1668 (49.4953, 41.3838) -> (49.3823, 41.2283)
  line L1669 (49.3823, 41.2283) -> (49.2464, 41.0923)
  line L1670 (49.2464, 41.0923) -> (49.0909, 40.9794)
  line L1671 (49.0909, 40.9794) -> (48.9196, 40.8921)
  line L1672 (48.9196, 40.8921) -> (48.7368, 40.8327)
  line L1673 (48.7368, 40.8327) -> (48.5469, 40.8026)
  line L1674 (48.5469, 40.8026) -> (48.3547, 40.8026)
  line L1675 (48.3547, 40.8026) -> (48.1648, 40.8327)
  line L1676 (48.1648, 40.8327) -> (47.982, 40.8921)
  line L1677 (47.982, 40.8921) -> (47.8107, 40.9794)
  line L1678 (47.8107, 40.9794) -> (47.6552, 41.0923)
  line L1679 (47.6552, 41.0923) -> (47.5193, 41.2283)
  line L1680 (47.5193, 41.2283) -> (47.4063, 41.3838)
  line L1681 (47.4063, 41.3838) -> (47.319, 41.5551)
  line L1682 (47.319, 41.5551) -> (47.2596, 41.7379)
  line L1683 (47.2596, 41.7379) -> (47.2296, 41.9277)
  line L1684 (47.2296, 41.9277) -> (47.2258, 42.0238)
  line L1685 (47.2258, 42.0238) -> (47.2258, 42.5738)
  line L1686 (47.2258, 42.5738) -> (47.2296, 42.6699)
  line L1687 (47.2296, 42.6699) -> (47.2596, 42.8598)
  line L1688 (47.2596, 42.8598) -> (47.319, 43.0426)
  line L1689 (47.319, 43.0426) -> (47.4063, 43.2139)
  line L1690 (47.4063, 43.2139) -> (47.5193, 43.3694)
  line L1691 (47.5193, 43.3694) -> (47.6552, 43.5053)
  line L1692 (47.6552, 43.5053) -> (47.8107, 43.6183)
  line L1693 (47.8107, 43.6183) -> (47.982, 43.7056)
  line L1694 (47.982, 43.7056) -> (48.1648, 43.765)
  line L1695 (48.1648, 43.765) -> (48.3547, 43.7951)
  line L1696 (48.3547, 43.7951) -> (48.5469, 43.7951)
  line L1697 (48.5469, 43.7951) -> (48.7368, 43.765)
  line L1698 (83.6618, 43.765) -> (83.8446, 43.7056)
  line L1699 (83.8446, 43.7056) -> (84.0159, 43.6183)
  line L1700 (84.0159, 43.6183) -> (84.1714, 43.5053)
  line L1701 (84.1714, 43.5053) -> (84.3073, 43.3694)
  line L1702 (84.3073, 43.3694) -> (84.4203, 43.2139)
  line L1703 (84.4203, 43.2139) -> (84.5076, 43.0426)
  line L1704 (84.5076, 43.0426) -> (84.567, 42.8598)
  line L1705 (84.567, 42.8598) -> (84.597, 42.6699)
  line L1706 (84.597, 42.6699) -> (84.6008, 42.5738)
  line L1707 (84.6008, 42.5738) -> (84.6008, 42.0238)
  line L1708 (84.6008, 42.0238) -> (84.597, 41.9277)
  line L1709 (84.597, 41.9277) -> (84.567, 41.7379)
  line L1710 (84.567, 41.7379) -> (84.5076, 41.555)
  line L1711 (84.5076, 41.555) -> (84.4203, 41.3838)
  line L1712 (84.4203, 41.3838) -> (84.3073, 41.2283)
  line L1713 (84.3073, 41.2283) -> (84.1714, 41.0923)
  line L1714 (84.1714, 41.0923) -> (84.0159, 40.9794)
  line L1715 (84.0159, 40.9794) -> (83.8446, 40.8921)
  line L1716 (83.8446, 40.8921) -> (83.6618, 40.8327)
  line L1717 (83.6618, 40.8327) -> (83.4719, 40.8026)
  line L1718 (83.4719, 40.8026) -> (83.2797, 40.8026)
  line L1719 (83.2797, 40.8026) -> (83.0898, 40.8327)
  line L1720 (83.0898, 40.8327) -> (82.907, 40.8921)
  line L1721 (82.907, 40.8921) -> (82.7357, 40.9794)
  line L1722 (82.7357, 40.9794) -> (82.5802, 41.0923)
  line L1723 (82.5802, 41.0923) -> (82.4443, 41.2283)
  line L1724 (82.4443, 41.2283) -> (82.3313, 41.3838)
  line L1725 (82.3313, 41.3838) -> (82.244, 41.5551)
  line L1726 (82.244, 41.5551) -> (82.1846, 41.7379)
  line L1727 (82.1846, 41.7379) -> (82.1546, 41.9277)
  line L1728 (82.1546, 41.9277) -> (82.1508, 42.0238)
  line L1729 (82.1508, 42.0238) -> (82.1508, 42.5738)
  line L1730 (82.1508, 42.5738) -> (82.1546, 42.6699)
  line L1731 (82.1546, 42.6699) -> (82.1846, 42.8598)
  line L1732 (82.1846, 42.8598) -> (82.244, 43.0426)
  line L1733 (82.244, 43.0426) -> (82.3313, 43.2139)
  line L1734 (82.3313, 43.2139) -> (82.4443, 43.3694)
  line L1735 (82.4443, 43.3694) -> (82.5802, 43.5053)
  line L1736 (82.5802, 43.5053) -> (82.7357, 43.6183)
  line L1737 (82.7357, 43.6183) -> (82.907, 43.7056)
  line L1738 (82.907, 43.7056) -> (83.0898, 43.765)
  line L1739 (83.0898, 43.765) -> (83.2797, 43.7951)
  line L1740 (83.2797, 43.7951) -> (83.4719, 43.7951)
  line L1741 (83.4719, 43.7951) -> (83.6618, 43.765)
  line L1742 (118.5868, 43.765) -> (118.7696, 43.7056)
  line L1743 (118.7696, 43.7056) -> (118.9409, 43.6183)
  line L1744 (118.9409, 43.6183) -> (119.0964, 43.5053)
  line L1745 (119.0964, 43.5053) -> (119.2323, 43.3694)
  line L1746 (119.2323, 43.3694) -> (119.3453, 43.2139)
  line L1747 (119.3453, 43.2139) -> (119.4326, 43.0426)
  line L1748 (119.4326, 43.0426) -> (119.492, 42.8598)
  line L1749 (119.492, 42.8598) -> (119.522, 42.6699)
  line L1750 (119.522, 42.6699) -> (119.5258, 42.5738)
  line L1751 (119.5258, 42.5738) -> (119.5258, 42.0238)
  line L1752 (119.5258, 42.0238) -> (119.522, 41.9277)
  line L1753 (119.522, 41.9277) -> (119.492, 41.7379)
  line L1754 (119.492, 41.7379) -> (119.4326, 41.555)
  line L1755 (119.4326, 41.555) -> (119.3453, 41.3838)
  line L1756 (119.3453, 41.3838) -> (119.2323, 41.2283)
  line L1757 (119.2323, 41.2283) -> (119.0964, 41.0923)
  line L1758 (119.0964, 41.0923) -> (118.9409, 40.9794)
  line L1759 (118.9409, 40.9794) -> (118.7696, 40.8921)
  line L1760 (118.7696, 40.8921) -> (118.5868, 40.8327)
  line L1761 (118.5868, 40.8327) -> (118.3969, 40.8026)
  line L1762 (118.3969, 40.8026) -> (118.2047, 40.8026)
  line L1763 (118.2047, 40.8026) -> (118.0148, 40.8327)
  line L1764 (118.0148, 40.8327) -> (117.832, 40.8921)
  line L1765 (117.832, 40.8921) -> (117.6607, 40.9794)
  line L1766 (117.6607, 40.9794) -> (117.5052, 41.0923)
  line L1767 (117.5052, 41.0923) -> (117.3693, 41.2283)
  line L1768 (117.3693, 41.2283) -> (117.2563, 41.3838)
  line L1769 (117.2563, 41.3838) -> (117.169, 41.5551)
  line L1770 (117.169, 41.5551) -> (117.1096, 41.7379)
  line L1771 (117.1096, 41.7379) -> (117.0796, 41.9277)
  line L1772 (117.0796, 41.9277) -> (117.0758, 42.0238)
  line L1773 (117.0758, 42.0238) -> (117.0758, 42.5738)
  line L1774 (117.0758, 42.5738) -> (117.0796, 42.6699)
  line L1775 (117.0796, 42.6699) -> (117.1096, 42.8598)
  line L1776 (117.1096, 42.8598) -> (117.169, 43.0426)
  line L1777 (117.169, 43.0426) -> (117.2563, 43.2139)
  line L1778 (117.2563, 43.2139) -> (117.3693, 43.3694)
  line L1779 (117.3693, 43.3694) -> (117.5052, 43.5053)
  line L1780 (117.5052, 43.5053) -> (117.6607, 43.6183)
  line L1781 (117.6607, 43.6183) -> (117.832, 43.7056)
  line L1782 (117.832, 43.7056) -> (118.0148, 43.765)
  line L1783 (118.0148, 43.765) -> (118.2047, 43.7951)
  line L1784 (118.2047, 43.7951) -> (118.3969, 43.7951)
  line L1785 (118.3969, 43.7951) -> (118.5868, 43.765)
  line L1786 (33.8595, 85.903) -> (34.046, 85.8424)
  line L1787 (34.046, 85.8424) -> (34.2208, 85.7533)
  line L1788 (34.2208, 85.7533) -> (34.3795, 85.638)
  line L1789 (34.3795, 85.638) -> (34.5182, 85.4993)
  line L1790 (34.5182, 85.4993) -> (34.6335, 85.3407)
  line L1791 (34.6335, 85.3407) -> (34.7225, 85.1659)
  line L1792 (34.7225, 85.1659) -> (34.7832, 84.9793)
  line L1793 (34.7832, 84.9793) -> (34.8138, 84.7856)
  line L1794 (34.8138, 84.7856) -> (34.8177, 84.6875)
  line L1795 (34.8177, 84.6875) -> (34.8177, 84.1875)
  line L1796 (34.8177, 84.1875) -> (34.8138, 84.0895)
  line L1797 (34.8138, 84.0895) -> (34.7832, 83.8957)
  line L1798 (34.7832, 83.8957) -> (34.7225, 83.7092)
  line L1799 (34.7225, 83.7092) -> (34.6335, 83.5344)
  line L1800 (34.6335, 83.5344) -> (34.5182, 83.3757)
  line L1801 (34.5182, 83.3757) -> (34.3795, 83.237)
  line L1802 (34.3795, 83.237) -> (34.2208, 83.1217)
  line L1803 (34.2208, 83.1217) -> (34.1677, 83.0947)
  line L1804 (34.1677, 83.0947) -> (34.1677, 78.9664)
  line L1805 (34.1677, 78.9664) -> (34.1626, 78.8881)
  line L1806 (34.1626, 78.8881) -> (34.122, 78.7368)
  line L1807 (34.122, 78.7368) -> (34.0437, 78.6011)
  line L1808 (34.0437, 78.6011) -> (33.992, 78.5421)
  line L1809 (33.992, 78.5421) -> (30.4416, 74.9918)
  line L1810 (30.4416, 74.9918) -> (30.4416, 74.2403)
  line L1811 (30.4416, 74.2403) -> (30.4368, 74.1423)
  line L1812 (30.4368, 74.1423) -> (30.3985, 73.95)
  line L1813 (30.3985, 73.95) -> (30.3235, 73.7689)
  line L1814 (30.3235, 73.7689) -> (30.2146, 73.6059)
  line L1815 (30.2146, 73.6059) -> (30.076, 73.4673)
  line L1816 (30.076, 73.4673) -> (30.0416, 73.4443)
  line L1817 (30.0416, 73.4443) -> (30.0416, 69.2882)
  line L1818 (30.0416, 69.2882) -> (30.0365, 69.2098)
  line L1819 (30.0365, 69.2098) -> (30.0009, 69.077)
  line L1820 (30.0009, 69.077) -> (29.9959, 69.0586)
  line L1821 (29.9959, 69.0586) -> (29.9947, 69.0564)
  line L1822 (29.9947, 69.0564) -> (29.9947, 67.9183)
  line L1823 (29.9947, 67.9183) -> (31.7386, 66.1744)
  line L1824 (31.7386, 66.1744) -> (34.1093, 66.1744)
  line L1825 (34.1093, 66.1744) -> (34.1876, 66.1692)
  line L1826 (34.1876, 66.1692) -> (34.3389, 66.1287)
  line L1827 (34.3389, 66.1287) -> (34.4745, 66.0504)
  line L1828 (34.4745, 66.0504) -> (34.5335, 65.9986)
  line L1829 (34.5335, 65.9986) -> (37.2692, 63.263)
  line L1830 (37.2692, 63.263) -> (37.3209, 63.204)
  line L1831 (37.3209, 63.204) -> (37.3992, 63.0683)
  line L1832 (37.3992, 63.0683) -> (37.4398, 62.9171)
  line L1833 (37.4398, 62.9171) -> (37.4449, 62.8387)
  line L1834 (37.4449, 62.8387) -> (37.4449, 56.2616)
  line L1835 (37.4449, 56.2616) -> (37.4398, 56.1833)
  line L1836 (37.4398, 56.1833) -> (37.3992, 56.032)
  line L1837 (37.3992, 56.032) -> (37.3209, 55.8963)
  line L1838 (37.3209, 55.8963) -> (37.2692, 55.8373)
  line L1839 (37.2692, 55.8373) -> (31.2159, 49.784)
  line L1840 (31.2159, 49.784) -> (31.1569, 49.7323)
  line L1841 (31.1569, 49.7323) -> (31.0212, 49.654)
  line L1842 (31.0212, 49.654) -> (30.8699, 49.6134)
  line L1843 (30.8699, 49.6134) -> (30.7916, 49.6083)
  line L1844 (30.7916, 49.6083) -> (16.5343, 49.6083)
  line L1845 (16.5343, 49.6083) -> (16.456, 49.6134)
  line L1846 (16.456, 49.6134) -> (16.3047, 49.654)
  line L1847 (16.3047, 49.654) -> (16.169, 49.7323)
  line L1848 (16.169, 49.7323) -> (16.11, 49.784)
  line L1849 (16.11, 49.784) -> (13.641, 52.2531)
  line L1850 (13.641, 52.2531) -> (12.7875, 52.2531)
  line L1851 (12.7875, 52.2531) -> (12.6783, 52.269)
  line L1852 (12.6783, 52.269) -> (12.5651, 52.3244)
  line L1853 (12.5651, 52.3244) -> (12.4759, 52.4135)
  line L1854 (12.4759, 52.4135) -> (12.4206, 52.5267)
  line L1855 (12.4206, 52.5267) -> (12.4047, 52.6359)
  line L1856 (12.4047, 52.6359) -> (12.4047, 54.8703)
  line L1857 (12.4047, 54.8703) -> (12.4206, 54.9795)
  line L1858 (12.4206, 54.9795) -> (12.4759, 55.0927)
  line L1859 (12.4759, 55.0927) -> (12.5651, 55.1819)
  line L1860 (12.5651, 55.1819) -> (12.6783, 55.2372)
  line L1861 (12.6783, 55.2372) -> (12.7875, 55.2531)
  line L1862 (12.7875, 55.2531) -> (14.4719, 55.2531)
  line L1863 (14.4719, 55.2531) -> (14.5811, 55.2372)
  line L1864 (14.5811, 55.2372) -> (14.6943, 55.1819)
  line L1865 (14.6943, 55.1819) -> (14.7834, 55.0927)
  line L1866 (14.7834, 55.0927) -> (14.8388, 54.9795)
  line L1867 (14.8388, 54.9795) -> (14.8547, 54.8703)
  line L1868 (14.8547, 54.8703) -> (14.8547, 52.7364)